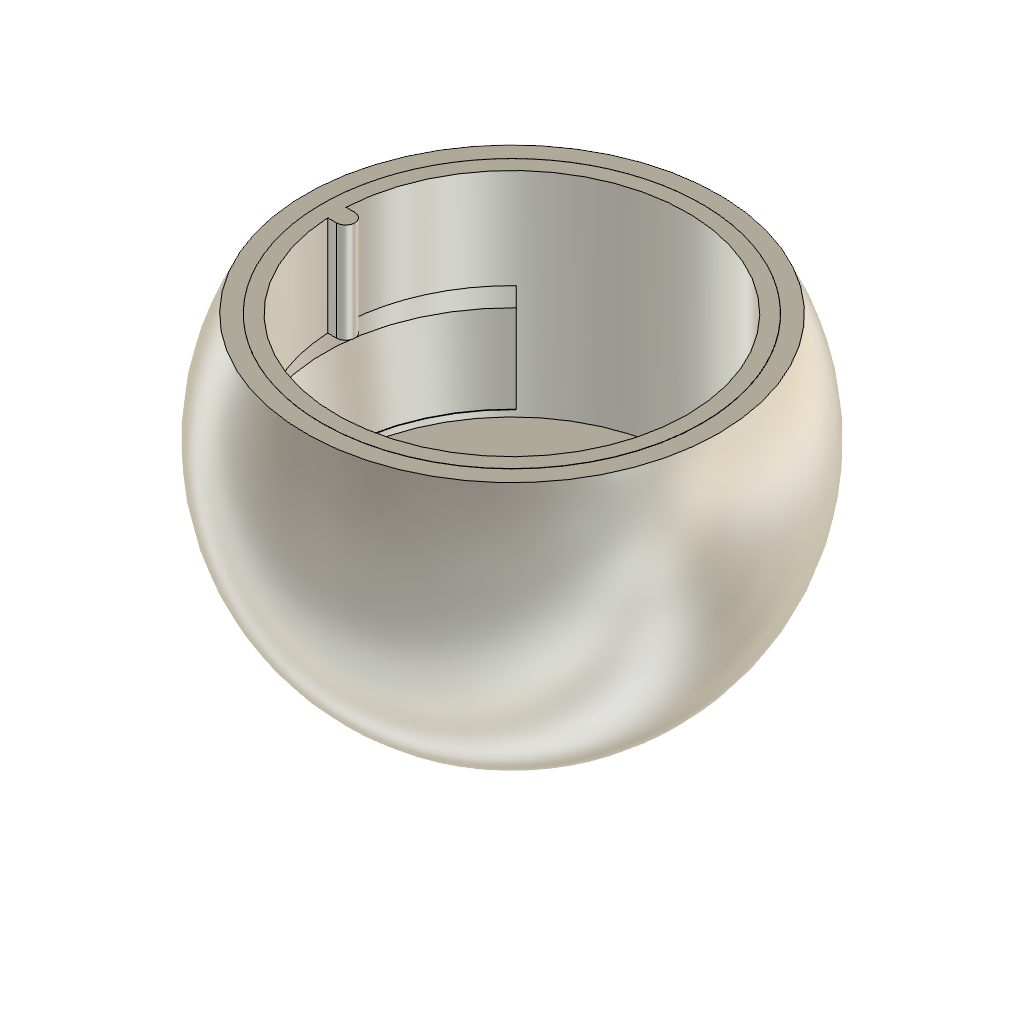
PlaceHolder Eye native (Autodesk Fusion 360 design; units mm, degrees)
part number: 2026-10-13-23-28-35-356
Autodesk Fusion 360 part; units mm, degrees
sketch "Shell" plane through (0, 0, 0) normal (0, 1, 0) x (1, 0, 0)
  line L0 (0.0087, -7.4931) -> (14.1544, -7.4931)
  arc A0 (14.1544, -7.4931) -> (0.0087, 16) centre (0.0175, 0) ccw
  line L1 (0.0087, 16) -> (0.0087, -7.4931)
  line L2 (0.0087, 16) -> (0.0087, -7.4931) construction
  dimension "d23" = 16
  dimension "d24" = 0.0175
  dimension "d25" = 0.0087
  dimension "d26" = 7.4931
  dimension "d27" = 0.0087
  dimension "d28" = 16
  dimension "d29" = 7.4931
  constraint horizontal L0
  constraint vertical L1
  constraint vertical L2
  constraint horizontal origin A0.centre
  measures "d23" radius of A0
  measures "d24" horizontal distance of origin A0.centre
  measures "d25" horizontal distance of origin L0.start
  measures "d26" vertical distance of origin L0.start
  measures "d27" horizontal distance of origin A0.end
  measures "d28" vertical distance of origin A0.end
  measures "d29" vertical distance of origin L0.start
revolve "Shell (1)" add sketch "Shell" angle 360 about axis through (0.0087, 0, -16) along (0, 0, 1)
move_body "Shell to STL frame" bodies 1 to x (1, 0, -0.000486) y (0, 1, 0) z (0.000486, 0, 1) at (0, 0, 0)
sketch "Eyeball" plane through (0, 0, 0) normal (0, 1, 0) x (1, 0, 0)
  line L0 (0, 0) -> (15, 0)
  arc A0 (12.9904, -7.5) -> (15, 0) centre (0, 0) ccw
  line L1 (12.9904, -7.5) -> (0, -7.5)
  line L2 (0, -7.5) -> (0, 0)
  line L3 (0, 0) -> (0, -7.5) construction
  dimension "d30" = 15
  dimension "d31" = 12.9904
  dimension "d32" = 7.5
  constraint horizontal L0
  constraint horizontal L1
  constraint vertical L2
  constraint vertical L3
  constraint coincident L0.start A0.centre
  constraint vertical L0.start A0.centre
  constraint horizontal L0.start A0.centre
  measures "d30" radius of A0
  measures "d31" horizontal distance of L0.start A0.start
  measures "d32" vertical distance of L0.start L1.end
revolve "Eyeball (1)" add sketch "Eyeball" angle 360 about axis through (0, 0, 0) along (0, 0, 1)
ref_plane "WorkPlane1" through (0, 0, 0.45) normal (0, 0, 1) x (1, 0, 0)
sketch "Bore" plane through (0, 0, 0.45) normal (0, 0, 1) x (1, 0, 0)
  circle A0 centre (0, 0) radius 11.9904
  dimension "d33" = 23.9808
  constraint coincident A0.centre origin
  measures "d33" diameter of A0
extrude "Bore (1)" cut sketch "Bore" along normal mid plane 15.1
ref_plane "WorkPlane2" through (0, 0, 4.088) normal (0, 0, 1) x (1, 0, 0)
sketch "Keying rib" plane through (0, 0, 4.088) normal (0, 0, 1) x (1, 0, 0)
  arc A0 (-11.3654, -0.625) -> (-11.3654, 0.625) centre (-11.3654, 0) ccw
  line L0 (-11.3654, 0.625) -> (-12.4904, 0.625)
  line L1 (-12.4904, 0.625) -> (-12.4904, -0.625)
  line L2 (-12.4904, -0.625) -> (-11.3654, -0.625)
  dimension "d34" = 0.625
  dimension "d35" = 11.3654
  dimension "d36" = 12.4904
  constraint horizontal L0
  constraint vertical L1
  constraint horizontal L2
  constraint tangent A0 L2
  constraint tangent A0 L0
  constraint horizontal origin A0.centre
  measures "d34" radius of A0
  measures "d35" horizontal distance of origin A0.centre
  measures "d36" horizontal distance of origin L0.end
extrude "Keying rib (1)" add sketch "Keying rib" along normal mid plane 6.824
ref_plane "WorkPlane3" through (0, 0, 12.125) normal (-0.642788, 0.766044, 0) x (0, 0, 1)
sketch "Recess 40" plane through (0, 0, 0) normal (-0.642788, 0.766044, 0) x (0, 0, 1)
  line L0 (0.6755, 11.5) -> (0.6755, 12.7904)
  line L1 (0.6755, 12.7904) -> (-1.2, 12.7904)
  line L2 (-1.2, 12.7904) -> (-6.671, 12.0378)
  line L3 (-6.671, 12.0378) -> (-6.671, 11.5)
  line L4 (-6.671, 11.5) -> (0.6755, 11.5)
  line L5 (-6.671, 0) -> (0.6755, 0) construction
  dimension "d37" = 0.6755
  dimension "d38" = 11.5
  dimension "d39" = 12.7904
  dimension "d40" = 1.2
  dimension "d41" = 6.671
  dimension "d42" = 12.0378
  dimension "d43" = 6.671
  dimension "d44" = 0.6755
  constraint vertical L0
  constraint horizontal L1
  constraint vertical L3
  constraint horizontal L4
  constraint horizontal L5
  constraint horizontal origin L5.start
  measures "d37" horizontal distance of origin L0.start
  measures "d38" vertical distance of origin L0.start
  measures "d39" vertical distance of origin L0.end
  measures "d40" horizontal distance of origin L1.end
  measures "d41" horizontal distance of origin L2.end
  measures "d42" vertical distance of origin L2.end
  measures "d43" horizontal distance of origin L5.start
  measures "d44" horizontal distance of origin L5.end
revolve "Recess 40 (1)" cut sketch "Recess 40" angle 21 about axis through (0, 0, -6.671) along (0, 0, 1) second angle 21
ref_plane "WorkPlane4" through (0, 0, 12.125) normal (0.642788, 0.766044, 0) x (0, 0, 1)
sketch "Recess -40" plane through (0, 0, 0) normal (0.642788, 0.766044, 0) x (0, 0, 1)
  line L0 (0.6755, 11.5) -> (0.6755, 12.7904)
  line L1 (0.6755, 12.7904) -> (-1.2, 12.7904)
  line L2 (-1.2, 12.7904) -> (-6.671, 12.0378)
  line L3 (-6.671, 12.0378) -> (-6.671, 11.5)
  line L4 (-6.671, 11.5) -> (0.6755, 11.5)
  line L5 (-6.671, 0) -> (0.6755, 0) construction
  dimension "d45" = 0.6755
  dimension "d46" = 11.5
  dimension "d47" = 12.7904
  dimension "d48" = 1.2
  dimension "d49" = 6.671
  dimension "d50" = 12.0378
  dimension "d51" = 6.671
  dimension "d52" = 0.6755
  constraint vertical L0
  constraint horizontal L1
  constraint vertical L3
  constraint horizontal L4
  constraint horizontal L5
  constraint horizontal origin L5.start
  measures "d45" horizontal distance of origin L0.start
  measures "d46" vertical distance of origin L0.start
  measures "d47" vertical distance of origin L0.end
  measures "d48" horizontal distance of origin L1.end
  measures "d49" horizontal distance of origin L2.end
  measures "d50" vertical distance of origin L2.end
  measures "d51" horizontal distance of origin L5.start
  measures "d52" horizontal distance of origin L5.end
revolve "Recess -40 (1)" cut sketch "Recess -40" angle 21 about axis through (0, 0, -6.671) along (0, 0, 1) second angle 21
ref_plane "WorkPlane5" through (0, 0, 12.125) normal (0, -1, 0) x (0, 0, 1)
sketch "Recess 180" plane through (0, 0, 0) normal (0, -1, 0) x (-1, 0, 0)
  line L0 (11.5, -0.6755) -> (12.7904, -0.6755)
  line L1 (12.7904, -0.6755) -> (12.7904, 1.2)
  line L2 (12.7904, 1.2) -> (12.0378, 6.671)
  line L3 (12.0378, 6.671) -> (11.5, 6.671)
  line L4 (11.5, 6.671) -> (11.5, -0.6755)
  line L5 (0, 6.671) -> (0, -0.6755) construction
  dimension "d53" = 11.5
  dimension "d54" = 0.6755
  dimension "d55" = 12.7904
  dimension "d56" = 1.2
  dimension "d57" = 12.0378
  dimension "d58" = 6.671
  dimension "d59" = 6.671
  dimension "d60" = 0.6755
  constraint horizontal L0
  constraint vertical L1
  constraint horizontal L3
  constraint vertical L4
  constraint vertical L5
  constraint vertical origin L5.start
  measures "d53" horizontal distance of origin L0.start
  measures "d54" vertical distance of origin L0.start
  measures "d55" horizontal distance of origin L0.end
  measures "d56" vertical distance of origin L1.end
  measures "d57" horizontal distance of origin L2.end
  measures "d58" vertical distance of origin L2.end
  measures "d59" vertical distance of origin L5.start
  measures "d60" vertical distance of origin L5.end
revolve "Recess 180 (1)" cut sketch "Recess 180" angle 46 about axis through (0, 0, -6.671) along (0, 0, 1) second angle 46
named bodies: "PlaceHolder Eye native"
